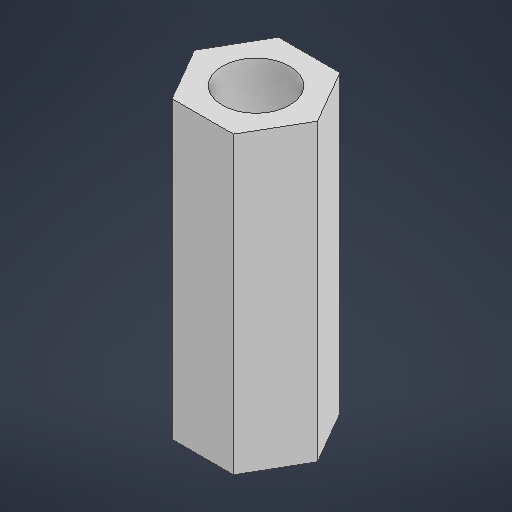
# Autodesk Inventor part: Plastic peg
Saved by Autodesk Inventor 2026.2 (Build 302298010, 298A)
## iProperties
Created: 2026-07-15
Part Number: Plastic peg
Material: Generic
Document SubType Name: Modeling
Designer: User
Density: 1 g/cm^3
Appearance: Default
Author: User
Autodesk Inventor part; units mm, degrees
ref_plane "YZ Plane" through (0, 0, 0) normal (1, 0, 0) x (0, 1, 0)
ref_plane "XZ Plane" through (0, 0, 0) normal (0, 1, 0) x (-1, 0, 0)
ref_plane "XY Plane" through (0, 0, 0) normal (0, 0, 1) x (1, 0, 0)
sketch "Sketch1" plane through (0, 0, 0) normal (0, 1, 0) x (-1, 0, 0)
  circle A0 centre (0, 0) radius 1.375
  line L0 (2.5, 0) -> (1.25, -2.1651)
  line L1 (2.5, 0) -> (5, 0) construction
  line L2 (1.25, -2.1651) -> (-1.25, -2.1651)
  line L3 (-1.25, -2.1651) -> (-2.5, 0)
  line L4 (-2.5, 0) -> (-1.25, 2.1651)
  line L5 (-1.25, 2.1651) -> (1.25, 2.1651)
  line L6 (1.25, 2.1651) -> (2.5, 0)
  dimension "d0" = 2.75
  dimension "d1" = 2.5
  dimension "d3" = 2.5
  dimension "d4" = 120
  dimension "d5" = 2.5
  constraints: 14 end point, 3 parallel, 2 horizontal, 1 centre point, 1 coincident, 1 equal length
  measures "d0" diameter of A0
  measures "d1" distance of A0.centre L0.start
  measures "d3" distance of L0.start L0.end
  measures "d4" angle of L0 L1
  measures "d5" distance of L0.end L2.end
extrude "Extrusion1" add sketch "Sketch1" along normal blind 12
body "Solid1"
